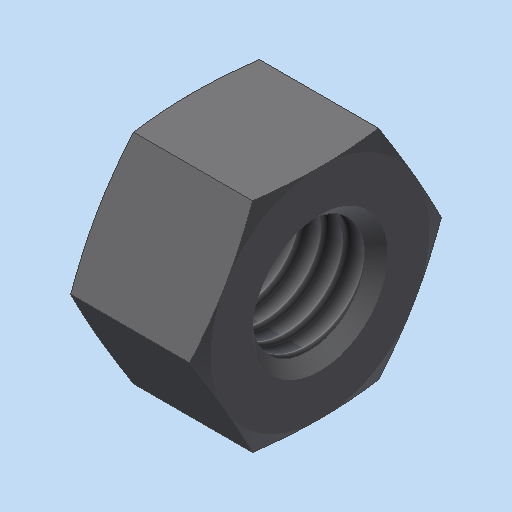
# Autodesk Inventor part: Sechskantmutter_ISO_4032___M5
Saved by Autodesk Inventor 2023.3 (Build 273359000, 359)
## iProperties
Shininess: 64.0
Length Units: 11269
Angle Units: 11279
Time Units: 11290
Mass Units: 11283
Length Display Precision: 3
Angle Display Precision: 2
Compacted: True
Part Number: Sechskantmutter_ISO_4032___M5
Document SubType Name: Modeling
Created: 2004-03-22
Material: xStahl_AnP_Dummymaterial
Description: =<RBPARTNOTITLE2>
Vendor: NORM8
Designer: S.Riedelsheimer
Manufacturer: Standard
Standards Organization: Custom
Density: 7.85 g/cm^3
Appearance: Stahl - normal AnP
Mass: 1.52521 g
Surface Area: 2.66409 cm^2
Volume: 0.194294 cm^3
DOC_ID: 5 F45 Sechskantmutter_ISO_4032___M5
GAIN_REFID: 20__Sechskantmutter_ISO_4032___M5:81C07
Control State: 0
Master: False
Checked Out: False
CNS_NB: Sechskantmutter ISO 4032 - M 5
CNS_NN: ISO 4032
CNS_NT: Sechskantmutter, Typ 1
CNS_NBSYN: Sechskantmutter ISO 4032 - $NENN.
CNS_LINA: Sechskantmutter ISO 4032 - M 5
CNS_NENN: M 5
CNS_D: 5.000
CNS_D1: 4.134
CNS_P: 0.800
CNS_M: 4.700
CNS_S: 8.000
CNS_KT: X
PSOL_IDENT_0: {C:\partsolutions8\data\23d-libs\bosch_bamberg\muttern\sechskantmuttern\din_iso_4032.prj},166 {M=Nen
PSOL_IDENT_1: ngewinde},{VTYP=3D},{NB=Sechskantmutter ISO 4032 - M 5},{NN=ISO 4032},{DATE=26.11.2003},{GEOMDATE=26
PSOL_IDENT_2: .11.2003},{VERSION=v2},{LINEID=60},{LINESUBID=-1},{WBVAR=}  {NB=Sechskantmutter ISO 4032 - M 5},{LIN
PSOL_IDENT_3: A=Sechskantmutter ISO 4032 - M 5},{KT=X},{IDNR=},{NENN=M 5},{D=5.000},{D1=4.134},{P=0.800},{M=4.700}
PSOL_IDENT_4: ,{S=8.000}
DEF_STKID: T20877
Bezeichnung1: Sechskantmutter ISO 4032 - M 5
Bezeichnung2: Sechskantmutter, Typ 1
RBPARTNOTITLE1: Hexagon regular nuts (style 1)
RBPARTNOTITLE2: Sechskantmuttern (Typ 1)
RBDRAWINGMISSINGSPEC: --
AnP_Kategorie: 5
RBPARTMADEOF: ISO 4032 - M5 - 8.8 - verzinkt
Density: 0.0
Volumn: 0.0
Area: 0.0
PropertySet Name: Model Information
Title: Sechskantmutter ISO 4032 - M 5
Author: S.Riedelsheimer
Keywords: =<RBPARTMADEOF>
Comments: =<RBSURFACE2>
Revision Number: 01
Autodesk Inventor part; units mm, degrees
sketch "Sketch_1" plane through (0, 0, 0) normal (0, 1, 0) x (-1, 0, 0)
  line L0 (0, 0) -> (-4.7, 0)
  line L1 (0, 4) -> (-2.35, 12.7703)
  line L2 (-2.35, 12.7703) -> (-4.7, 4)
  line L3 (-4.7, 4) -> (-4.7, 2.5)
  line L4 (-4.7, 2.5) -> (-4.267, 2.067)
  line L5 (-4.267, 2.067) -> (-0.433, 2.067)
  line L6 (-0.433, 2.067) -> (0, 2.5)
  line L7 (0, 2.5) -> (0, 4)
  constraints: 16 end point
revolve "Drehung1" add sketch "Sketch_1" angle 360 about axis through (0, 0, 0) along (-1, 0, 0)
thread "Gewinde1" size "M5x0.8" class "6H" standard "ANSI Metric M Profile" length 4.7
sketch "Sketch_2" plane through (0, 0, 0) normal (1, 0, 0) x (0, 1, 0)
  line L0 (-16, 16) -> (-16, -16)
  line L1 (-16, -16) -> (16, -16)
  line L2 (16, -16) -> (16, 16)
  line L3 (16, 16) -> (-16, 16)
  line L4 (-2.3094, 4) -> (-4.6188, 0)
  line L5 (-4.6188, 0) -> (-2.3094, -4)
  line L6 (-2.3094, -4) -> (2.3094, -4)
  line L7 (2.3094, -4) -> (4.6188, 0)
  line L8 (4.6188, 0) -> (2.3094, 4)
  line L9 (2.3094, 4) -> (-2.3094, 4)
  constraints: 20 end point
extrude "Extrusion1" cut sketch "Sketch_2" along normal mid plane 11.4
ref_plane "IP1_XY" through (0, 0, 0) normal (1, 0, 0) x (0, 0, -1)
ref_plane "IP1_YZ" through (0, 0, 0) normal (0, 0, -1) x (0, 1, 0)
ref_plane "IP2_XY" through (4.7, 0, 0) normal (1, 0, 0) x (0, 0, -1)
ref_plane "IP2_YZ" through (4.7, 0, 0) normal (0, 0, -1) x (0, 1, 0)
